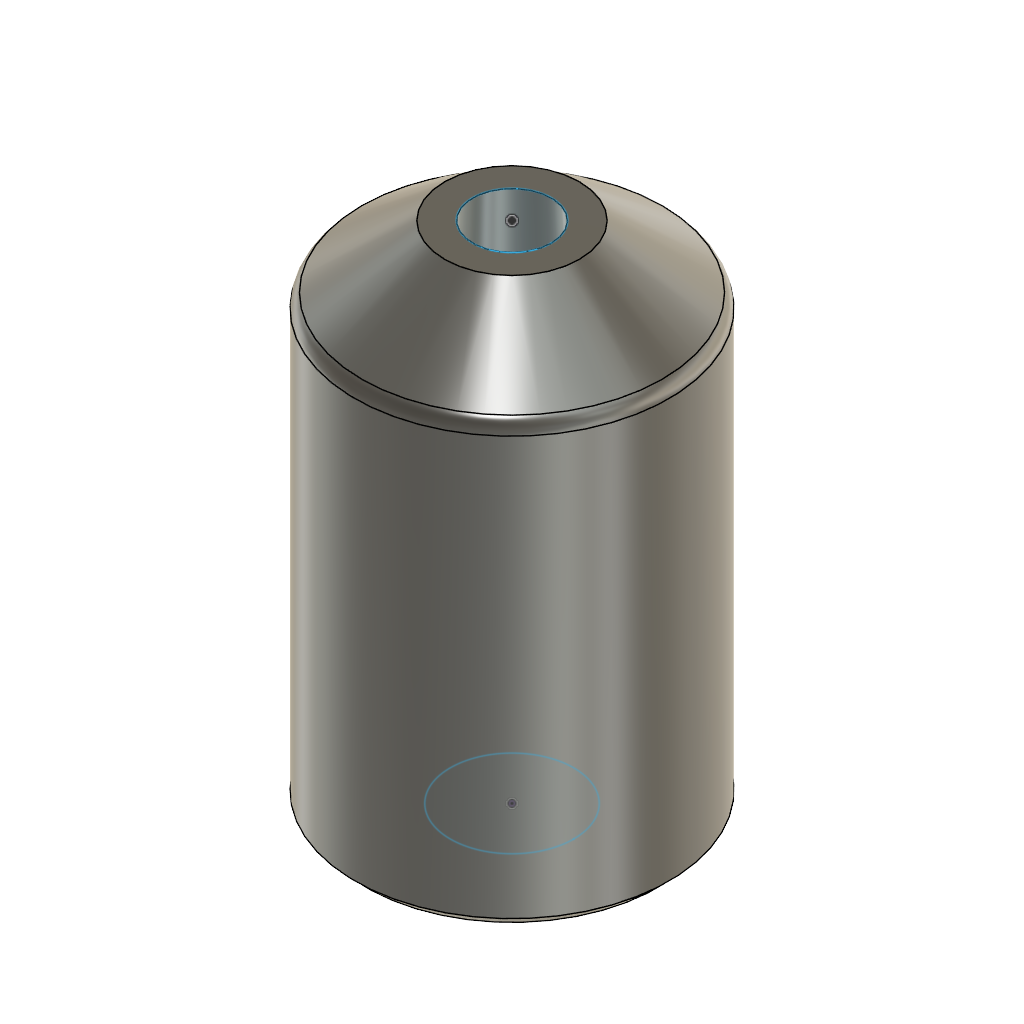
pen-grip_v0.1 (Autodesk Fusion 360 design; units mm, degrees)
part number: 2026-11-10-14-22-55-646
Autodesk Fusion 360 part; units mm, degrees
ref_plane "WorkPlane1" through (0, 0, 45) normal (0, 0, 1) x (1, 0, 0)
sketch "Outer" plane through (0, 0, 0) normal (0, 0, 1) x (1, 0, 0)
  circle A0 centre (0, 0) radius 14
  dimension "d11" = 28
  constraint coincident A0.centre origin
  measures "d11" diameter of A0
extrude "GripBody" add sketch "Outer" along normal blind 45
chamfer "NoseCone" distance 8 distance2 6 1 edges at (-13.0526, -5.0626, 45) measured on face at (4.6394, 2.5701, 45) tangent chain off
chamfer "BaseChamfer" distance 1 angle 45 1 edges at (-13.0526, -5.0626, 0) tangent chain off
sketch "BoreBack" plane through (0, 0, 0) normal (0, 0, 1) x (1, 0, 0)
  circle A0 centre (0, 0) radius 5.5
  dimension "d17" = 11
  constraint coincident A0.centre origin
  measures "d17" diameter of A0
sketch "BoreNose" plane through (0, 0, 45) normal (0, 0, 1) x (1, 0, 0)
  circle A0 centre (0, 0) radius 3.5
  dimension "d18" = 7
  constraint coincident A0.centre origin
  measures "d18" diameter of A0
loft "TaperedBore" cut profiles "BoreBack", "BoreNose" section 1 section 2
fillet "NoseBlend" radius 1.5 1 edges at (-13.0526, -5.0626, 39)
equation "grip_od = 28 mm" comment "Grip outer diameter. M = 28 mm, outer diameter of the larger closed-cell foam built-up tubing sold for pens and cutlery"
equation "grip_len = 45 mm" comment "Grip length along the pen (design estimate: covers the finger contact zone)"
equation "bore_wide = 11 mm" comment "Bore at the back end (design estimate; brackets the 8 mm equivalent-diameter pen of Goonetilleke et al. 2009)"
equation "bore_narrow = 7 mm" comment "Bore at the nose: pens taper toward the tip and wedge here (design estimate - check your pen)"
equation "nose_h = 6 mm" comment "Height of the nose cone at the writing end"
equation "nose_in = grip_od / 2 - bore_narrow / 2 - 2.5 mm" comment "Radial step of the nose cone; leaves 2.5 mm of wall at the tip"
equation "base_chamfer = 1 mm" comment "45 deg chamfer on the bed edge"
equation "nose_r = 1.5 mm" comment "Comfort fillet where the nose cone meets the barrel"
equation "d9 = grip_len"
equation "d11 = grip_od"
equation "d12 = grip_len"
equation "d14 = nose_in"
equation "d15 = nose_h"
equation "d16 = base_chamfer"
equation "d17 = bore_wide"
equation "d18 = bore_narrow"
equation "d20 = nose_r"
named bodies: "PenGrip"
